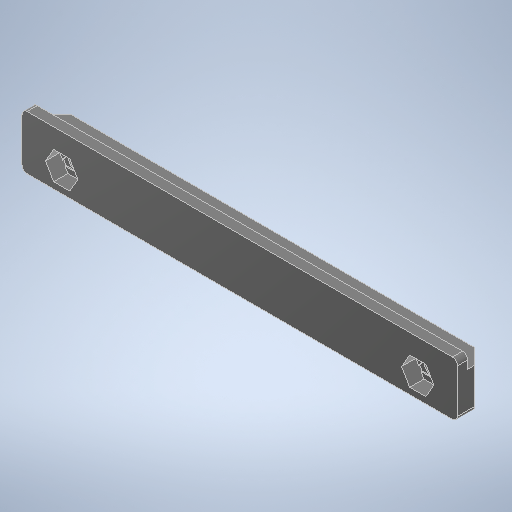
# Autodesk Inventor part: 3D_XT30-fix
Saved by Autodesk Inventor 2025.3 (Build 293356030, 356C)
## iProperties
Created: 2025-09-04
Part Number: 3D_XT30-fix
Material: 一般
Document SubType Name: Modeling
Designer: ibuki_ono
Density: 1 g/cm^3
Appearance: 滑らか - 黒
Author: ibuki_ono
## iProperties of the stored document 3D_XT30-fix_3D プリント.ipt
Created: 2025-09-04
Part Number: 3D_XT30-fix_3D プリント
Material: 一般
Document SubType Name: Modeling
Designer: ibuki_ono
Density: 1 g/cm^3
Appearance: 既定
Author: ibuki_ono
Autodesk Inventor part; units mm, degrees
ref_plane "YZ Plane" through (0, 0, 0) normal (1, 0, 0) x (0, 1, 0)
ref_plane "XZ Plane" through (0, 0, 0) normal (0, 1, 0) x (-1, 0, 0)
ref_plane "XY Plane" through (0, 0, 0) normal (0, 0, 1) x (1, 0, 0)
sketch "スケッチ1" plane through (0, 0, 0) normal (0, 0, 1) x (1, 0, 0)
  line L0 (-42.8, -5.3) -> (42.8, -5.3)
  line L1 (42.8, -5.3) -> (42.8, 5.3)
  line L2 (42.8, 5.3) -> (-42.8, 5.3)
  line L3 (-42.8, 5.3) -> (-42.8, -5.3)
  line L4 (-42.8, -5.3) -> (42.8, 5.3) construction
  line L5 (42.8, -5.3) -> (-42.8, 5.3) construction
  point P0 (0, 0)
  dimension "d0" = 85.6
  dimension "d1" = 10.6
  constraints: 12 end point, 2 midpoint, 2 parallel, 1 horizontal, 1 perpendicular
  measures "d0" distance of L2.end L1.end
  measures "d1" distance of L1.end L0.end
extrude "押し出し1" add sketch "スケッチ1" along normal blind 2
sketch "スケッチ2" plane through (0, 0, 0) normal (0, 0, -1) x (-1, 0, 0)
  line L0 (-42.8, -5.3) -> (-42.8, 5.3) projected
  line L1 (42.8, -5.3) -> (-42.8, -5.3) projected
  line L2 (42.8, 5.3) -> (42.8, -5.3) projected
  line L3 (-42.8, 5.3) -> (42.8, 5.3) projected
  line L4 (-42.8, -5.3) -> (-42.8, 5.3) projected
  line L5 (-42.8, 2.7) -> (42.8, 2.7)
  point P0 (0, 0)
  dimension "d4" = 2.6
  constraints: 2 end point, 2 point on line, 1 perpendicular
  measures "d4" distance between parallel lines of L3 L5
extrude "押し出し2" add sketch "スケッチ2" along normal blind 4.4 contours L0 L5 L2 L1
sketch "スケッチ3" plane through (0, 0, -4.4) normal (0, 0, -1) x (-1, 0, 0)
  line L0 (-42.8, 2.7) -> (-42.8, -5.3) projected
  line L1 (42.8, -5.3) -> (42.8, 2.7) projected
  line L2 (-42.8, -1.3) -> (42.8, -1.3) construction
  point P0 (0, 0)
  point P1 (-35, -1.3)
  point P2 (35, -1.3)
  dimension "d7" = 35
  dimension "d8" = 35
  constraints: 2 end point, 2 midpoint, 2 point on line
  measures "d7" horizontal distance of point (-35, -1.3) point (0, 0)
  measures "d8" horizontal distance of point (0, 0) point (35, -1.3)
hole "穴1" at (35, -1.3, -4.4) at (-35, -1.3, -4.4) direction (0, 0, 1) diameter 3.5 end through all
sketch "スケッチ4" plane through (0, 0, 2) normal (0, 0, 1) x (1, 0, 0)
  circle A0 centre (35, -1.3) radius 1.75 projected
  line L0 (31.8246, -1.3) -> (33.4123, 1.45)
  line L1 (33.4123, 1.45) -> (36.5877, 1.45)
  line L2 (36.5877, 1.45) -> (38.1754, -1.3)
  line L3 (38.1754, -1.3) -> (36.5877, -4.05)
  line L4 (36.5877, -4.05) -> (33.4123, -4.05)
  line L5 (33.4123, -4.05) -> (31.8246, -1.3)
  point P0 (0, 0)
  dimension "d16" = 5.5
  constraints: 12 end point, 1 coincident, 1 horizontal alignment, 13 other
  measures "d16" distance between parallel lines of L1 L4
extrude "押し出し3" cut sketch "スケッチ4" against normal blind 2.8
sketch "スケッチ5" plane through (0, 0, -0.8) normal (0, 0, 1) x (1, 0, 0)
  line L0 (36.5877, -4.05) -> (33.4123, -4.05) projected
  line L1 (36.5877, -4.05) -> (33.4123, -4.05) projected
  line L2 (38.1754, -1.3) -> (36.5877, -4.05) projected
  line L3 (36.5877, 1.45) -> (38.1754, -1.3) projected
  line L4 (33.4123, 1.45) -> (36.5877, 1.45) projected
  line L5 (31.8246, -1.3) -> (33.4123, 1.45) projected
  line L6 (33.4123, -4.05) -> (31.8246, -1.3) projected
  circle A0 centre (35, -1.3) radius 1.75 projected
  line L7 (37.1651, -3.05) -> (32.8349, -3.05)
  line L8 (33.4123, -4.05) -> (31.8246, -1.3) projected
  line L9 (32.4019, -2.3) -> (34.567, 1.45)
  line L10 (35.433, 1.45) -> (37.5981, -2.3)
  line L11 (36.5877, 1.45) -> (38.1754, -1.3) projected
  line L12 (31.8246, -1.3) -> (33.4123, 1.45) projected
  circle A1 centre (35, -1.3) radius 1.75 projected
  point P0 (0, 0)
  point P1 (36.5155, -0.425)
  point P2 (33.4845, -0.425)
  point P3 (35, -3.05)
  constraints: 6 end point, 6 point on line, 3 parallel, 3 tangent, 1 horizontal
extrude "押し出し4" cut sketch "スケッチ5" against normal blind 0.2 contours L7 A0 L10 L2 | L6 L9 A0 L7 | A0 L9 L4 L10
mirror "ミラー1" about plane through (0, 0, 0) normal (1, 0, 0) of "押し出し3", "押し出し4"
chamfer "面取り1" distance 3.1 angle 45 2 edges at (42.8, -1.3, -4.4) (-42.8, -1.3, -4.4)
fillet "フィレット2" radius 1 4 edges at (-42.8, -5.3, 0.35) (-42.8, 5.3, 1) (42.8, 5.3, 1) (42.8, -5.3, 0.35)
equation "\"d8\" = d7"
